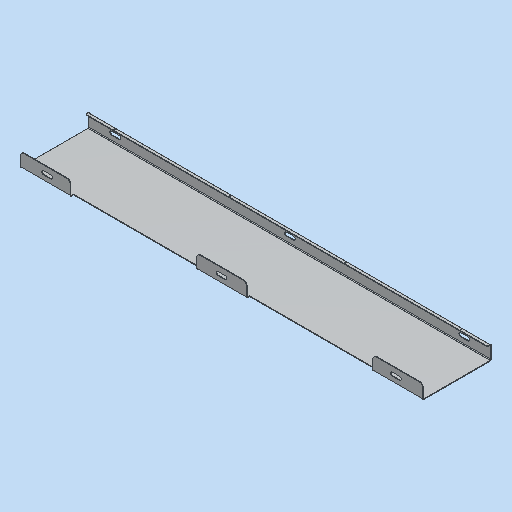
# Autodesk Inventor part: SE0004AN000_G01_100
Saved by Autodesk Inventor 2023.3 (Build 273359000, 359)
## iProperties
Part Number: SE0004AN000_G01_100
Material: 3.1645 AlCu4PbMgMn - AW 2007
Description: =<RBPARTNOTITLE2>
Document SubType Name: Blech
Designer: Benutzer
Mass: 1817.4 g
Surface Area: 6450.8 cm^2
Volume: 637.685 cm^3
Density: 2.85 g/cm^3
Sheet Metal Rule: Standard_mm
Appearance: Aluminium AnP
Vendor: ASW
Flat Pattern Width: 29.5572 cm
Flat Pattern Length: 121.2 cm
Flat Pattern Area: 3582.33 cm^2
Sheet Metal Width: 295,572 mm
Sheet Metal Length: 1212,000 mm
Sheet Metal Area: 358232,876 mm^2
RBCHANGEDESCRIPTION1: Erstfreigabe
RBCHANGENO1: 00
RBDOCUMENTTYPE: DRF
RBDOCUMENTVERSION: 00
RBDRAWINGMAINSCALE: 1:1
RBDRAWINGMISSINGSPEC: --
RBDRAWINGVOLUME: --
RBDSV1: 0850
RBGBDETAILS: 43274
RBGBEDGESIN1: +0,5
RBGBEDGESIN2: +0,2
RBGBEDGESOUT1: -0,3
RBGBEDGESOUT2: -0,1
RBMATERIAL: =<Material>
RBMATMEETS: --
RBMATNO: =<Part Number>
RBORGUNITRESPONSIBLE1: AnP/TEF1
RBPARTMADEOF: 43 x 208 x 1212 (FM)
RBPARTNO: SIEHE MNR
RBPARTNOTITLE1: manufactured part
RBPARTNOTITLE2: Anfertigungsteil
RBPARTSAFETYINDICATOR: --
RBSURFACE: --
RBSURFACE2: --
RBZEDGESNORM: ISO13715:2002-06
RBZGENDIMCLASS: m
RBZGENDIMNORM: ISO 2768-1:1989-11
RBZGENGEOCLASS: H
RBZGENGEONORM: ISO 2768-2:1989-11
RBZSURFACENORM: ISO13D2:2002-02
RBZTOLERANCENORM: ISO 14405-1:2010-12
AnP_Material: =<Material>
AnP_TemplVers: 20190222
AnP_Kategorie: 1
MaxAbmaße: 43 x 208 x 1212 (FM)
Author: Benutzer
Keywords: =<RBPARTMADEOF>
Comments: =<RBSURFACE2>
Revision Number: 01
Autodesk Inventor part; units mm, degrees
ref_plane "YZ Plane" through (0, 0, 0) normal (1, 0, 0) x (0, 1, 0)
ref_plane "XZ Plane" through (0, 0, 0) normal (0, 1, 0) x (-1, 0, 0)
ref_plane "XY Plane" through (0, 0, 0) normal (0, 0, 1) x (1, 0, 0)
sketch "Skizze1" plane through (0, 0, 0) normal (0, 0, 1) x (1, 0, 0)
  line L0 (0, 0) -> (1212, 0)
  line L1 (1212, 0) -> (1212, 208)
  line L2 (1212, 208) -> (0, 208)
  line L3 (0, 208) -> (0, 0)
  dimension "d0" = 1212
  dimension "d1" = 208
  constraints: 8 end point, 2 parallel, 1 horizontal, 1 perpendicular
  measures "d0" distance of L2.end L1.end
  measures "d1" distance of L1.end L0.end
extrude "Extrusion1" add sketch "Skizze1" along normal blind 2
sketch "Skizze2" plane through (1212, 2, 0) normal (0, -1, 0) x (1, 0, 0)
  line L0 (-1212, 0) -> (0, 0)
  line L1 (0, 0) -> (0, 43)
  line L2 (0, 43) -> (-1212, 43)
  line L3 (-1212, 43) -> (-1212, 0)
  constraints: 4 end point, 4 other
edge flange "Lasche1" height 43 angle 90 thickness 2 bend radius 2 thickness toward (0, -1, 0) relief tear relief width 2 relief depth 1 corner gap 2 corner form 0 edges at (606, 0, 2) (606, 208, 2) wall of the first edge with corners at (0, 2, 0) (1212, 2, 0) (1212, 2, 43) (0, 2, 43)
bend "Biegung1"
corner "Ecke1"
sketch "Skizze3" plane through (0, 208, 41) normal (0, 0, 1) x (1, 0, 0)
  line L0 (1212, 0) -> (0, 0)
  line L1 (0, 0) -> (0, -12)
  line L2 (0, -12) -> (1212, -12)
  line L3 (1212, -12) -> (1212, 0)
  constraints: 4 end point, 4 other
edge flange "Lasche2" height 12 angle 90 thickness 2 bend radius 2 thickness toward (0, 0, 1) relief tear relief width 2 relief depth 1 edges at (606, 206, 43) wall of the first edge with corners at (1212, 208, 41) (0, 208, 41) (0, 196, 41) (1212, 196, 41)
bend "Biegung2"
corner "Ecke2"
sketch "Skizze5" plane through (0, 0, 4) normal (0, -1, 0) x (1, 0, 0)
  line L0 (69, 18.5) -> (91, 18.5) construction
  line L1 (69, 13) -> (91, 13)
  line L2 (91, 24) -> (69, 24)
  arc A0 (69, 24) -> (69, 13) centre (69, 18.5) ccw
  arc A1 (91, 13) -> (91, 24) centre (91, 18.5) ccw
  line L3 (1121, 18.5) -> (1143, 18.5) construction
  line L4 (1121, 13) -> (1143, 13)
  line L5 (1143, 24) -> (1121, 24)
  arc A2 (1121, 24) -> (1121, 13) centre (1121, 18.5) ccw
  arc A3 (1143, 13) -> (1143, 24) centre (1143, 18.5) ccw
  line L6 (1212, -4) -> (0, -4) projected
  line L7 (0, 0) -> (0, 39) projected
  line L8 (1212, 39) -> (1212, 0) projected
  point P0 (80, 18.5)
  point P1 (1132, 18.5)
  dimension "d29" = 22
  dimension "d30" = 11
  dimension "d31" = 22
  dimension "d32" = 11
  dimension "d33" = 22.5
  dimension "d34" = 80
  dimension "d35" = 80
  constraints: 16 end point, 8 point on circle, 8 tangent, 4 centre point, 2 midpoint, 2 parallel, 2 point on line, 1 horizontal
  measures "d29" distance of L0.start L0.end
  measures "d30" diameter of A1
  measures "d31" distance of L3.start L3.end
  measures "d32" diameter of A3
  measures "d33" distance from line of point (80, 18.5) L6
  measures "d34" distance from line of point (80, 18.5) L7
  measures "d35" distance from line of L8 point (1132, 18.5)
extrude "Extrusion3" cut sketch "Skizze5" against normal through all
sketch "Skizze8" plane through (0, 0, 4) normal (0, -1, 0) x (1, 0, 0)
  line L0 (595, 18.5) -> (617, 18.5) construction
  line L1 (595, 13) -> (617, 13)
  line L2 (617, 24) -> (595, 24)
  arc A0 (595, 24) -> (595, 13) centre (595, 18.5) ccw
  arc A1 (617, 13) -> (617, 24) centre (617, 18.5) ccw
  line L3 (0, 47.6) -> (0, -12.6) projected
  line L4 (69, 24) -> (91, 24) projected
  line L5 (1212, -4) -> (0, -4) projected
  point P0 (606, 18.5)
  dimension "d61" = 22
  dimension "d62" = 11
  dimension "d63" = 606
  dimension "d64" = 22.5
  constraints: 8 end point, 4 point on circle, 4 tangent, 2 centre point, 1 horizontal, 1 midpoint, 1 parallel
  measures "d61" distance of L0.start L0.end
  measures "d62" diameter of A1
  measures "d63" distance from line of L3 point (606, 18.5)
  measures "d64" distance from line of point (606, 18.5) L5
extrude "Extrusion5" cut sketch "Skizze8" against normal through all
fillet "Rundung1" radius 10 2 edges at (0, 1, 43) (1212, 1, 43)
fillet "Rundung2" radius 5 2 edges at (1212, 196, 42) (0, 196, 42)
sketch "Skizze10" plane through (0, 204, 43) normal (0, 0, 1) x (1, 0, 0)
  line L0 (1212, 0) -> (0, 0) projected
  line L1 (1207, -8) -> (5, -8) projected
  line L2 (0, 45.6) -> (0, -245.6) projected
  line L3 (0, 4) -> (1212, 4) projected
  point P0 (0, -204)
  point P1 (84, -4)
  dimension "d77" = 84
  dimension "d78" = 8
  measures "d77" distance from line of point (84, -4) L2
  measures "d78" distance from line of point (84, -4) L3
hole "Bohrung2" at (84, 200, 43) direction (0, 0, -1) diameter 3.242 depth 11.8 tip angle 118 thread size "M4x0.7" designation "M4" class "6H" standard "ISO Metric profile"
pattern_linear "Rechteckige Anordnung1" count 5 spacing 348 along (1, 0, 0) of "Bohrung2"
sketch "Skizze11" plane through (0, 0, 4) normal (0, -1, 0) x (1, 0, 0)
  arc A0 (1212, 29) -> (1202, 39) centre (1202, 29) ccw projected
  line L0 (10, 39) -> (1202, 39) projected
  arc A1 (10, 39) -> (0, 29) centre (10, 29) ccw projected
  line L1 (0, 0) -> (0, 29) projected
  line L2 (0, 0) -> (1212, 0) projected
  line L3 (1212, 29) -> (1212, 0) projected
  arc A2 (617, 13) -> (617, 24) centre (617, 18.5) ccw projected
  line L4 (617, 13) -> (595, 13) projected
  arc A3 (595, 24) -> (595, 13) centre (595, 18.5) ccw projected
  line L5 (595, 24) -> (617, 24) projected
  arc A4 (91, 13) -> (91, 24) centre (91, 18.5) ccw projected
  line L6 (91, 13) -> (69, 13) projected
  arc A5 (69, 24) -> (69, 13) centre (69, 18.5) ccw projected
  line L7 (69, 24) -> (91, 24) projected
  arc A6 (1143, 13) -> (1143, 24) centre (1143, 18.5) ccw projected
  line L8 (1143, 13) -> (1121, 13) projected
  arc A7 (1121, 24) -> (1121, 13) centre (1121, 18.5) ccw projected
  line L9 (1121, 24) -> (1143, 24) projected
  line L10 (1212, -4) -> (0, -4) projected
  line L11 (150, 39) -> (531, 39)
  line L12 (531, 39) -> (531, -11)
  line L13 (531, -11) -> (150, -11)
  line L14 (150, -11) -> (150, 39)
  line L15 (681, 39) -> (1062, 39)
  line L16 (1062, 39) -> (1062, -11)
  line L17 (1062, -11) -> (681, -11)
  line L18 (681, -11) -> (681, 39)
  point P0 (871.5, -11)
  point P1 (340.5, -11)
  point P2 (531, 39)
  dimension "d90" = 50
  dimension "d91" = 150
  dimension "d92" = 150
  dimension "d93" = 150
  dimension "d96" = 1212
  dimension "d97" = 531
  constraints: 16 end point, 4 parallel, 2 horizontal, 2 midpoint, 2 perpendicular, 2 point on line, 1 horizontal alignment
  measures "d90" distance between parallel lines of L13 L11
  measures "d91" distance between parallel lines of L14 L1
  measures "d92" distance between parallel lines of L18 L12
  measures "d93" distance between parallel lines of L3 L16
  measures "d96" distance between parallel lines of L3 L1
  measures "d97" distance between parallel lines of L3 L18
extrude "Extrusion7" cut sketch "Skizze11" against normal blind 10 contours L16 L2 L18 L0 | L16 L10 L18 L2 | L16 L17 L18 L10 | L12 L2 L14 L0 | L12 L10 L14 L2 | L12 L13 L14 L10
fillet "Rundung3" radius 10 4 edges at (150, 1, 43) (531, 1, 43) (681, 1, 43) (1062, 1, 43)
equation "\"d97\" = -0.5 * d92 + 0.5 * d96"
equation "\"d4\" = BreiteBiegungsfreistellung"
equation "\"d5\" = TiefeBiegungsfreistellung"
equation "\"d6\" = MinimalRest"
equation "\"d7\" = Biegeradius"
equation "\"d10\" = Biegeradius"
equation "\"d11\" = GrößeEckenfreistellung"
equation "\"d12\" = Abstandsgröße"
equation "\"d13\" = JacobiRadiusGröße"
equation "\"d89\" = Stärke"
equation "\"d14\" = BreiteBiegungsfreistellung"
equation "\"d15\" = TiefeBiegungsfreistellung"
equation "\"d16\" = MinimalRest"
equation "\"d17\" = Biegeradius"
equation "\"d20\" = Biegeradius"
equation "\"d21\" = GrößeEckenfreistellung"
equation "\"d22\" = Abstandsgröße"
equation "\"d23\" = JacobiRadiusGröße"
equation "\"Biegeradius\" = Stärke"
equation "\"BreiteBiegungsfreistellung\" = Stärke"
equation "\"TiefeBiegungsfreistellung\" = 0.5 * Stärke"
equation "\"GrößeEckenfreistellung\" = 4 * Stärke"
equation "\"MinimalRest\" = 2 * Stärke"
equation "\"Übergangsradius\" = Biegeradius"
equation "\"JacobiRadiusGröße\" = Biegeradius"
equation "\"Abstandsgröße\" = Stärke"
equation "\"Stärke\" = 2"
